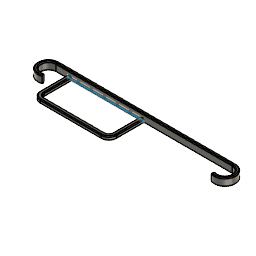
brashes hook (Autodesk Fusion 360 design; units mm, degrees)
part number: 2026-09-13-19-58-23-760
Autodesk Fusion 360 part; units mm, degrees
sketch "Sketch1" plane through (0, 0, 0) normal (0, 0, 1) x (1, 0, 0)
  line L0 (0, 9.5) -> (112.5, 9.5)
  line L1 (0, 0) -> (0, 9.5) construction
  line L2 (0, 13.5) -> (112.5, 13.5)
  line L3 (112.5, 33.3682) -> (112.5, -19) construction
  line L4 (0, 0) -> (3.2492, -8.9271) construction
  line L5 (0, 0) -> (13.5, 0) construction
  arc A0 (3.2492, -8.9271) -> (0, 9.5) centre (0, 0) ccw construction
  arc A1 (0, 9.5) -> (3.2492, -8.9271) centre (0, 0) ccw
  arc A2 (4.6173, -12.6859) -> (0, 13.5) centre (0, 0) ccw construction
  arc A3 (0, 13.5) -> (4.6173, -12.6859) centre (0, 0) ccw
  line L6 (3.2492, -8.9271) -> (4.6173, -12.6859)
  line L7 (112.5, 13.5) -> (112.5, 9.5) construction
  line L8 (225, 13.5) -> (112.5, 13.5)
  line L9 (225, 9.5) -> (112.5, 9.5)
  arc A4 (220.3827, -12.6859) -> (225, 13.5) centre (225, 0) ccw
  arc A5 (221.7508, -8.9271) -> (225, 9.5) centre (225, 0) ccw
  line L10 (221.7508, -8.9271) -> (220.3827, -12.6859)
  line L11 (110, 9.5) -> (115, 9.5)
  dimension "d3" = 112.5
  dimension "d6" = -4
  dimension "d122" = 19
  dimension "d124" = 70
  constraint horizontal L0
  constraint perpendicular L2 L3
  constraint coincident L1.start L4.start
  constraint horizontal L5
  constraint symmetric L0.start L3 L9.start
  constraint symmetric L0.end L3 L7.end
  constraint symmetric L2.end L3 L7.start
  constraint symmetric L2.start L3 L8.start
  constraint symmetric L3 A2.start A4.start
  constraint symmetric L3 L4.end A5.start
  constraint symmetric L3 A1 A5
  constraint symmetric L3 A3 A4
  constraint coincident L0 L11.start
  constraint coincident L9 L11.end
  measures "d3" distance of L0.start L0.end
  measures "d122" diameter of A0
  measures "d124" angle of L4 L5
extrude "Extrude1" add sketch "Sketch1" along normal blind 10
sketch "Sketch8" plane through (0, 9.5, 0) normal (0, -1, 0) x (1, 0, 0)
  line L0 (0, 0) -> (225, 0)
  line L1 (225, 10) -> (0, 10)
  line L2 (112.5, 10) -> (112.5, 0) construction
  line L3 (14.9878, 5) -> (112.5, 5)
  line L4 (112.5, 5) -> (112.5, 0)
  line L5 (112.5, 0) -> (14.9878, 0)
  line L6 (14.9878, 0) -> (14.9878, 5)
  line L7 (225, 0) -> (225, 10)
  line L8 (0, 10) -> (0, 0)
  constraint midpoint L1 L2.start
  constraint midpoint L0 L2.end
  constraint horizontal L3
  constraint vertical L4
  constraint horizontal L5
  constraint vertical L6
extrude "Extrude7" add sketch "Sketch8" along normal blind 45 contours L0 L3 L4 L5 L6
fillet "Fillet4" radius 10 2 edges at (14.9878, -35.5, 2.5) (112.5, -35.5, 2.5)
sketch "Sketch9" plane through (0, 0, 5) normal (0, 0, 1) x (-1, 0, 0)
  arc A0 (-102.5, 35.5) -> (-112.5, 25.5) centre (-102.5, 25.5) ccw
  line L0 (-112.5, 25.5) -> (-112.5, -9.5)
  line L1 (-112.5, -9.5) -> (-14.9878, -9.5)
  line L2 (-14.9878, -9.5) -> (-14.9878, 25.5)
  arc A1 (-14.9878, 25.5) -> (-24.9878, 35.5) centre (-24.9878, 25.5) ccw
  line L3 (-24.9878, 35.5) -> (-102.5, 35.5)
  line L4 (-24.9878, 30.5) -> (-102.5, 30.5)
  arc A2 (-102.5, 30.5) -> (-107.5, 25.5) centre (-102.5, 25.5) ccw
  line L5 (-107.5, 25.5) -> (-107.5, -9.5)
  line L6 (-19.9878, -9.5) -> (-19.9878, 25.5)
  arc A3 (-19.9878, 25.5) -> (-24.9878, 30.5) centre (-24.9878, 25.5) ccw
  dimension "d105" = -5
  constraint coincident L1 L6.start
  constraint coincident L1 L5.end
extrude "Extrude8" cut sketch "Sketch9" against normal up to surface (5 mm away) contours L1 L4 A2 L5 L6 A3
chamfer "Chamfer4" distance 1 angle 45 14 edges at (112.5, 13.5, 10) (238.2949, -2.3443, 10) (-13.2949, -2.3443, 10) (112.5, 9.5, 10) (-9.3557, -1.6497, 10) (234.3557, -1.6497, 10) (112.5, 13.5, 0) (238.2949, -2.3443, 0) (-13.2949, -2.3443, 0) (168.75, 9.5, 0) (234.3557, -1.6497, 0) (63.7439, 9.5, 0) (7.4939, 9.5, 0) (-9.3557, -1.6497, 0) tangent chain off
chamfer "Chamfer5" distance 1 angle 45 20 edges at (19.9878, -8, 5) (107.5, -8, 5) (106.0355, -29.0355, 5) (63.7439, -30.5, 5) (21.4522, -29.0355, 5) (14.9878, -8, 5) (17.9167, -32.5711, 5) (63.7439, -35.5, 5) (109.5711, -32.5711, 5) (112.5, -8, 5) (17.9167, -32.5711, 0) (63.7439, -35.5, 0) (109.5711, -32.5711, 0) (112.5, -7.5, 0) (14.9878, -7.5, 0) (63.7439, -30.5, 0) (106.0355, -29.0355, 0) (107.5, -8, 0) (19.9878, -8, 0) (21.4522, -29.0355, 0) tangent chain off
sketch "Sketch11" plane through (0, 9.5, 0) normal (0, -1, 0) x (1, 0, 0)
  line L0 (15, 5.056) -> (112.5185, 5.056) construction
  line L1 (112.5185, 5.056) -> (112.5185, 0.044) construction
  line L2 (112.5185, 0.044) -> (15, 0.044) construction
  line L3 (15, 0.044) -> (15, 5.056) construction
  line L4 (15, 2.55) -> (112.5185, 2.55) construction
  line L5 (15.5, 2.3) -> (111.9984, 2.3)
  line L6 (15.5, 2.8) -> (111.9984, 2.8)
  line L7 (111.9984, 2.8) -> (111.9984, 2.3) construction
  line L8 (111.9984, 2.8) -> (111.9984, 2.3)
  line L9 (15.5, 2.8) -> (15.5, 2.3)
  dimension "d118" = 0.25
  dimension "d119" = -0.25
  constraint horizontal L0
  constraint vertical L1
  constraint horizontal L2
  constraint vertical L3
  constraint midpoint L3 L4.start
  constraint midpoint L1 L4.end
  constraint perpendicular L5 L7
  constraint perpendicular L5 L9
extrude "Extrude10" cut sketch "Sketch11" against normal blind 2
